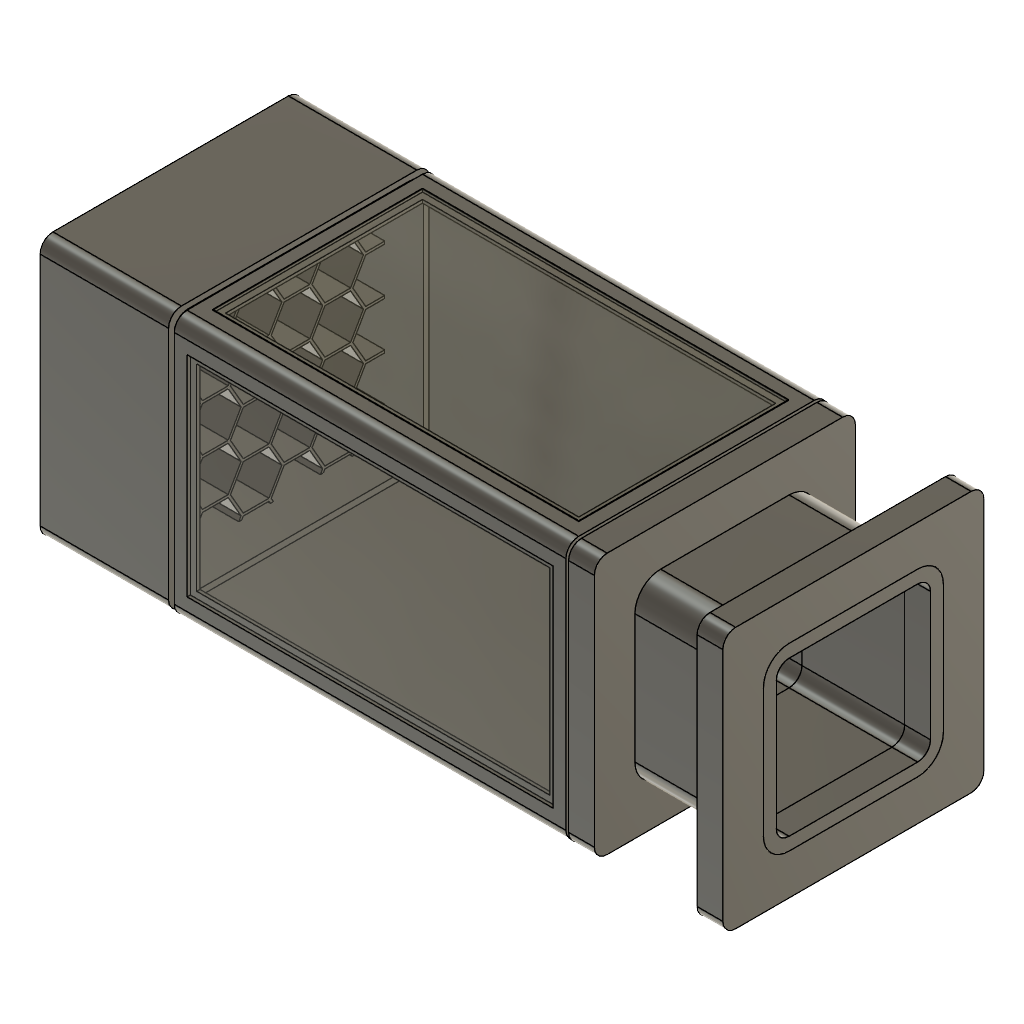
Wind Tunnel Design (Autodesk Fusion 360 design; units mm, degrees)
part number: 2026-09-10-14-34-11-708
Autodesk Fusion 360 part; units mm, degrees
sketch "Sketch6" plane through (0, 0, 0) normal (0, 1, 0) x (1, 0, 0)
  line L0 (-10, -16) -> (173.2, -16)
  line L1 (183.2, -6) -> (183.2, 177.2)
  line L2 (173.2, 187.2) -> (-10, 187.2)
  line L3 (-20, 177.2) -> (-20, -6)
  arc A0 (-20, -6) -> (-10, -16) centre (-10, -6) ccw
  arc A1 (173.2, -16) -> (183.2, -6) centre (173.2, -6) ccw
  arc A2 (183.2, 177.2) -> (173.2, 187.2) centre (173.2, 177.2) ccw
  arc A3 (-10, 187.2) -> (-20, 177.2) centre (-10, 177.2) ccw
  point P0 (-20, -16)
  point P1 (183.2, -16)
  point P2 (-20, 187.2)
  dimension "d24" = 203.2
  dimension "d25" = 203.2
  dimension "d26" = 10
  constraint horizontal L0
  constraint vertical L1
  constraint horizontal L2
  constraint vertical L3
  constraint coincident P0 L0
  constraint coincident P0 L3
  constraint tangent L0 A0
  constraint tangent L3 A0
  constraint coincident P1 L0
  constraint coincident P1 L1
  constraint tangent L0 A1
  constraint tangent L1 A1
  constraint equal A0 A1
  constraint tangent L1 A2
  constraint tangent L2 A2
  constraint equal A0 A2
  constraint coincident P2 L2
  constraint coincident P2 L3
  constraint tangent L2 A3
  constraint tangent L3 A3
  constraint equal A0 A3
  measures "d24" distance of P0 P1
  measures "d25" distance of P0 P2
  measures "d26" radius of A0
extrude "Extrude11" add sketch "Sketch6" along normal blind 100 makes body 1
move_body "Move1" bodies 1 to x (1, 0, 0) y (0, 1, 0) z (0, 0, 1) at (0, 0, 185)
move_face "MoveFace1" by (0, 0, 10) 1 faces at (47.7333, 0, 129.9333) on bodies 1
move_body "Move2" bodies 1 to x (1, 0, 0) y (0, 1, 0) z (0, 0, 1) at (0, 0, 2)
sketch "Sketch7" plane through (0, 0, 0) normal (0, -1, 0) x (1, 0, 0)
  arc A0 (-20, 9.8) -> (-10, -0.2) centre (-10, 9.8) ccw
  line L0 (-10, -0.2) -> (173.2, -0.2)
  arc A1 (173.2, -0.2) -> (183.2, 9.8) centre (173.2, 9.8) ccw
  line L1 (183.2, 9.8) -> (183.2, 193)
  arc A2 (183.2, 193) -> (173.2, 203) centre (173.2, 193) ccw
  line L2 (173.2, 203) -> (-10, 203)
  arc A3 (-10, 203) -> (-20, 193) centre (-10, 193) ccw
  line L3 (-20, 193) -> (-20, 9.8)
  line L4 (-5, 198.5) -> (168.2, 198.5)
  line L5 (178.2, 188.5) -> (178.2, 15.3)
  line L6 (168.2, 5.3) -> (-5, 5.3)
  line L7 (-15, 15.3) -> (-15, 188.5)
  arc A4 (-5, 198.5) -> (-15, 188.5) centre (-5, 188.5) ccw
  arc A5 (178.2, 188.5) -> (168.2, 198.5) centre (168.2, 188.5) ccw
  arc A6 (-15, 15.3) -> (-5, 5.3) centre (-5, 15.3) ccw
  arc A7 (168.2, 5.3) -> (178.2, 15.3) centre (168.2, 15.3) ccw
  point P0 (-15, 198.5)
  point P1 (178.2, 198.5)
  point P2 (-15, 5.3)
  dimension "d29" = 193.2
  dimension "d30" = 193.2
  dimension "d31" = 10
  dimension "d32" = 10
  constraint horizontal L4
  constraint vertical L5
  constraint horizontal L6
  constraint vertical L7
  constraint coincident P0 L4
  constraint coincident P0 L7
  constraint tangent L4 A4
  constraint tangent L7 A4
  constraint coincident P1 L4
  constraint coincident P1 L5
  constraint tangent L4 A5
  constraint tangent L5 A5
  constraint equal A4 A5
  constraint coincident P2 L6
  constraint coincident P2 L7
  constraint tangent L6 A6
  constraint tangent L7 A6
  constraint tangent L5 A7
  constraint tangent L6 A7
  constraint equal A6 A7
  measures "d29" distance of P0 P1
  measures "d30" distance of P0 P2
  measures "d31" radius of A4
  measures "d32" radius of A6
extrude "Extrude12" cut sketch "Sketch7" against normal blind 100 contours L4 L5 L6 L7 A4 A5 A6 A7 bodies 1
sketch "Sketch8" plane through (0, 0, 0) normal (0, -1, 0) x (1, 0, 0)
  line L0 (-15, 200) -> (180, 200)
  line L1 (180, 200) -> (180, 5)
  line L2 (180, 5) -> (-15, 5)
  line L3 (-15, 5) -> (-15, 200)
  line L4 (20.942, 156.3504) -> (32.4034, 176.3996)
  line L5 (32.4034, 176.3996) -> (20.771, 196.3501)
  line L6 (20.771, 196.3501) -> (-2.3228, 196.2513)
  line L7 (-2.3228, 196.2513) -> (-13.7842, 176.2022)
  line L8 (-13.7842, 176.2022) -> (-2.1518, 156.2517)
  line L9 (-2.1518, 156.2517) -> (20.942, 156.3504)
  point P0 (9.3096, 176.3009)
  dimension "d35" = 20
  constraint horizontal L0
  constraint vertical L1
  constraint horizontal L2
  constraint vertical L3
  measures "d35" distance of P0 L9
sketch "Sketch9" plane through (0, 0, 0) normal (0, -1, 0) x (1, 0, 0)
  line L0 (168.2, 5.3) -> (-5, 5.3)
  arc A0 (-15, 15.3) -> (-5, 5.3) centre (-5, 15.3) ccw
  line L1 (-15, 15.3) -> (-15, 188.5)
  arc A1 (-5, 198.5) -> (-15, 188.5) centre (-5, 188.5) ccw
  line L2 (-5, 198.5) -> (168.2, 198.5)
  arc A2 (178.2, 188.5) -> (168.2, 198.5) centre (168.2, 188.5) ccw
  line L3 (178.2, 188.5) -> (178.2, 15.3)
  arc A3 (168.2, 5.3) -> (178.2, 15.3) centre (168.2, 15.3) ccw
  arc A4 (-20, 9.8) -> (-10, -0.2) centre (-10, 9.8) ccw
  line L4 (-10, -0.2) -> (173.2, -0.2)
  arc A5 (173.2, -0.2) -> (183.2, 9.8) centre (173.2, 9.8) ccw
  line L5 (183.2, 9.8) -> (183.2, 193)
  arc A6 (183.2, 193) -> (173.2, 203) centre (173.2, 193) ccw
  line L6 (173.2, 203) -> (-10, 203)
  arc A7 (-10, 203) -> (-20, 193) centre (-10, 193) ccw
  line L7 (-20, 193) -> (-20, 9.8)
  line L8 (95.0575, 82.6796) -> (105.0575, 100.0001)
  line L9 (105.0575, 100.0001) -> (95.0575, 117.3206)
  line L10 (95.0575, 117.3206) -> (75.0575, 117.3206)
  line L11 (75.0575, 117.3206) -> (65.0575, 100.0001)
  line L12 (65.0575, 100.0001) -> (75.0575, 82.6796)
  line L13 (75.0575, 82.6796) -> (95.0575, 82.6796)
  line L14 (105.0575, 100.0001) -> (113.7178, 95.0001)
  line L15 (126.7939, 99.0019) -> (106.7939, 99.0019)
  line L16 (106.7939, 99.0019) -> (96.7939, 81.6814)
  line L17 (96.7939, 81.6814) -> (106.7939, 64.3609)
  line L18 (106.7939, 64.3609) -> (126.7939, 64.3609)
  line L19 (126.7939, 64.3609) -> (136.7939, 81.6814)
  line L20 (136.7939, 81.6814) -> (126.7939, 99.0019)
  line L21 (232.0575, -9.9499) -> (222.0575, 7.3706)
  line L22 (222.0575, 7.3706) -> (202.0575, 7.3706)
  line L23 (202.0575, 7.3706) -> (192.0575, -9.9499)
  line L24 (192.0575, -9.9499) -> (202.0575, -27.2704)
  line L25 (202.0575, -27.2704) -> (222.0575, -27.2704)
  line L26 (222.0575, -27.2704) -> (232.0575, -9.9499)
  line L27 (223.7939, -28.2686) -> (233.7939, -45.5891)
  line L28 (233.7939, -45.5891) -> (253.7939, -45.5891)
  line L29 (253.7939, -45.5891) -> (263.7939, -28.2686)
  line L30 (263.7939, -28.2686) -> (253.7939, -10.9481)
  line L31 (233.7939, -10.9481) -> (223.7939, -28.2686)
  line L32 (253.7939, -10.9481) -> (233.7939, -10.9481)
  line L33 (168.5575, -9.9499) -> (158.5575, 7.3706)
  line L34 (158.5575, 7.3706) -> (138.5575, 7.3706)
  line L35 (138.5575, 7.3706) -> (128.5575, -9.9499)
  line L36 (128.5575, -9.9499) -> (138.5575, -27.2704)
  line L37 (138.5575, -27.2704) -> (158.5575, -27.2704)
  line L38 (158.5575, -27.2704) -> (168.5575, -9.9499)
  line L39 (160.2939, -28.2686) -> (170.2939, -45.5891)
  line L40 (170.2939, -45.5891) -> (190.2939, -45.5891)
  line L41 (190.2939, -45.5891) -> (200.2939, -28.2686)
  line L42 (200.2939, -28.2686) -> (190.2939, -10.9481)
  line L43 (170.2939, -10.9481) -> (160.2939, -28.2686)
  line L44 (190.2939, -10.9481) -> (170.2939, -10.9481)
  line L45 (105.0575, -9.9499) -> (95.0575, 7.3706)
  line L46 (95.0575, 7.3706) -> (75.0575, 7.3706)
  line L47 (75.0575, 7.3706) -> (65.0575, -9.9499)
  line L48 (65.0575, -9.9499) -> (75.0575, -27.2704)
  line L49 (75.0575, -27.2704) -> (95.0575, -27.2704)
  line L50 (95.0575, -27.2704) -> (105.0575, -9.9499)
  line L51 (96.7939, -28.2686) -> (106.7939, -45.5891)
  line L52 (106.7939, -45.5891) -> (126.7939, -45.5891)
  line L53 (126.7939, -45.5891) -> (136.7939, -28.2686)
  line L54 (136.7939, -28.2686) -> (126.7939, -10.9481)
  line L55 (106.7939, -10.9481) -> (96.7939, -28.2686)
  line L56 (126.7939, -10.9481) -> (106.7939, -10.9481)
  line L57 (41.5575, -9.9499) -> (31.5575, 7.3706)
  line L58 (31.5575, 7.3706) -> (11.5575, 7.3706)
  line L59 (11.5575, 7.3706) -> (1.5575, -9.9499)
  line L60 (1.5575, -9.9499) -> (11.5575, -27.2704)
  line L61 (11.5575, -27.2704) -> (31.5575, -27.2704)
  line L62 (31.5575, -27.2704) -> (41.5575, -9.9499)
  line L63 (33.2939, -28.2686) -> (43.2939, -45.5891)
  line L64 (43.2939, -45.5891) -> (63.2939, -45.5891)
  line L65 (63.2939, -45.5891) -> (73.2939, -28.2686)
  line L66 (73.2939, -28.2686) -> (63.2939, -10.9481)
  line L67 (43.2939, -10.9481) -> (33.2939, -28.2686)
  line L68 (63.2939, -10.9481) -> (43.2939, -10.9481)
  line L69 (-21.9425, -9.9499) -> (-31.9425, 7.3706)
  line L70 (-31.9425, 7.3706) -> (-51.9425, 7.3706)
  line L71 (-51.9425, 7.3706) -> (-61.9425, -9.9499)
  line L72 (-61.9425, -9.9499) -> (-51.9425, -27.2704)
  line L73 (-51.9425, -27.2704) -> (-31.9425, -27.2704)
  line L74 (-31.9425, -27.2704) -> (-21.9425, -9.9499)
  line L75 (-30.2061, -28.2686) -> (-20.2061, -45.5891)
  line L76 (-20.2061, -45.5891) -> (-0.2061, -45.5891)
  line L77 (-0.2061, -45.5891) -> (9.7939, -28.2686)
  line L78 (9.7939, -28.2686) -> (-0.2061, -10.9481)
  line L79 (-20.2061, -10.9481) -> (-30.2061, -28.2686)
  line L80 (-0.2061, -10.9481) -> (-20.2061, -10.9481)
  line L81 (232.0575, 26.7001) -> (222.0575, 44.0206)
  line L82 (222.0575, 44.0206) -> (202.0575, 44.0206)
  line L83 (202.0575, 44.0206) -> (192.0575, 26.7001)
  line L84 (192.0575, 26.7001) -> (202.0575, 9.3796)
  line L85 (202.0575, 9.3796) -> (222.0575, 9.3796)
  line L86 (222.0575, 9.3796) -> (232.0575, 26.7001)
  line L87 (223.7939, 8.3814) -> (233.7939, -8.9391)
  line L88 (233.7939, -8.9391) -> (253.7939, -8.9391)
  line L89 (253.7939, -8.9391) -> (263.7939, 8.3814)
  line L90 (263.7939, 8.3814) -> (253.7939, 25.7019)
  line L91 (233.7939, 25.7019) -> (223.7939, 8.3814)
  line L92 (253.7939, 25.7019) -> (233.7939, 25.7019)
  line L93 (168.5575, 26.7001) -> (158.5575, 44.0206)
  line L94 (158.5575, 44.0206) -> (138.5575, 44.0206)
  line L95 (138.5575, 44.0206) -> (128.5575, 26.7001)
  line L96 (128.5575, 26.7001) -> (138.5575, 9.3796)
  line L97 (138.5575, 9.3796) -> (158.5575, 9.3796)
  line L98 (158.5575, 9.3796) -> (168.5575, 26.7001)
  line L99 (160.2939, 8.3814) -> (170.2939, -8.9391)
  line L100 (170.2939, -8.9391) -> (190.2939, -8.9391)
  line L101 (190.2939, -8.9391) -> (200.2939, 8.3814)
  line L102 (200.2939, 8.3814) -> (190.2939, 25.7019)
  line L103 (170.2939, 25.7019) -> (160.2939, 8.3814)
  line L104 (190.2939, 25.7019) -> (170.2939, 25.7019)
  line L105 (105.0575, 26.7001) -> (95.0575, 44.0206)
  line L106 (95.0575, 44.0206) -> (75.0575, 44.0206)
  line L107 (75.0575, 44.0206) -> (65.0575, 26.7001)
  line L108 (65.0575, 26.7001) -> (75.0575, 9.3796)
  line L109 (75.0575, 9.3796) -> (95.0575, 9.3796)
  line L110 (95.0575, 9.3796) -> (105.0575, 26.7001)
  line L111 (96.7939, 8.3814) -> (106.7939, -8.9391)
  line L112 (106.7939, -8.9391) -> (126.7939, -8.9391)
  line L113 (126.7939, -8.9391) -> (136.7939, 8.3814)
  line L114 (136.7939, 8.3814) -> (126.7939, 25.7019)
  line L115 (106.7939, 25.7019) -> (96.7939, 8.3814)
  line L116 (126.7939, 25.7019) -> (106.7939, 25.7019)
  line L117 (41.5575, 26.7001) -> (31.5575, 44.0206)
  line L118 (31.5575, 44.0206) -> (11.5575, 44.0206)
  line L119 (11.5575, 44.0206) -> (1.5575, 26.7001)
  line L120 (1.5575, 26.7001) -> (11.5575, 9.3796)
  line L121 (11.5575, 9.3796) -> (31.5575, 9.3796)
  line L122 (31.5575, 9.3796) -> (41.5575, 26.7001)
  line L123 (33.2939, 8.3814) -> (43.2939, -8.9391)
  line L124 (43.2939, -8.9391) -> (63.2939, -8.9391)
  line L125 (63.2939, -8.9391) -> (73.2939, 8.3814)
  line L126 (73.2939, 8.3814) -> (63.2939, 25.7019)
  line L127 (43.2939, 25.7019) -> (33.2939, 8.3814)
  line L128 (63.2939, 25.7019) -> (43.2939, 25.7019)
  line L129 (-21.9425, 26.7001) -> (-31.9425, 44.0206)
  line L130 (-31.9425, 44.0206) -> (-51.9425, 44.0206)
  line L131 (-51.9425, 44.0206) -> (-61.9425, 26.7001)
  line L132 (-61.9425, 26.7001) -> (-51.9425, 9.3796)
  line L133 (-51.9425, 9.3796) -> (-31.9425, 9.3796)
  line L134 (-31.9425, 9.3796) -> (-21.9425, 26.7001)
  line L135 (-30.2061, 8.3814) -> (-20.2061, -8.9391)
  line L136 (-20.2061, -8.9391) -> (-0.2061, -8.9391)
  line L137 (-0.2061, -8.9391) -> (9.7939, 8.3814)
  line L138 (9.7939, 8.3814) -> (-0.2061, 25.7019)
  line L139 (-20.2061, 25.7019) -> (-30.2061, 8.3814)
  line L140 (-0.2061, 25.7019) -> (-20.2061, 25.7019)
  line L141 (232.0575, 63.3501) -> (222.0575, 80.6706)
  line L142 (222.0575, 80.6706) -> (202.0575, 80.6706)
  line L143 (202.0575, 80.6706) -> (192.0575, 63.3501)
  line L144 (192.0575, 63.3501) -> (202.0575, 46.0296)
  line L145 (202.0575, 46.0296) -> (222.0575, 46.0296)
  line L146 (222.0575, 46.0296) -> (232.0575, 63.3501)
  line L147 (223.7939, 45.0314) -> (233.7939, 27.7109)
  line L148 (233.7939, 27.7109) -> (253.7939, 27.7109)
  line L149 (253.7939, 27.7109) -> (263.7939, 45.0314)
  line L150 (263.7939, 45.0314) -> (253.7939, 62.3519)
  line L151 (233.7939, 62.3519) -> (223.7939, 45.0314)
  line L152 (253.7939, 62.3519) -> (233.7939, 62.3519)
  line L153 (168.5575, 63.3501) -> (158.5575, 80.6706)
  line L154 (158.5575, 80.6706) -> (138.5575, 80.6706)
  line L155 (138.5575, 80.6706) -> (128.5575, 63.3501)
  line L156 (128.5575, 63.3501) -> (138.5575, 46.0296)
  line L157 (138.5575, 46.0296) -> (158.5575, 46.0296)
  line L158 (158.5575, 46.0296) -> (168.5575, 63.3501)
  line L159 (160.2939, 45.0314) -> (170.2939, 27.7109)
  line L160 (170.2939, 27.7109) -> (190.2939, 27.7109)
  line L161 (190.2939, 27.7109) -> (200.2939, 45.0314)
  line L162 (200.2939, 45.0314) -> (190.2939, 62.3519)
  line L163 (170.2939, 62.3519) -> (160.2939, 45.0314)
  line L164 (190.2939, 62.3519) -> (170.2939, 62.3519)
  line L165 (105.0575, 63.3501) -> (95.0575, 80.6706)
  line L166 (95.0575, 80.6706) -> (75.0575, 80.6706)
  line L167 (75.0575, 80.6706) -> (65.0575, 63.3501)
  line L168 (65.0575, 63.3501) -> (75.0575, 46.0296)
  line L169 (75.0575, 46.0296) -> (95.0575, 46.0296)
  line L170 (95.0575, 46.0296) -> (105.0575, 63.3501)
  line L171 (96.7939, 45.0314) -> (106.7939, 27.7109)
  line L172 (106.7939, 27.7109) -> (126.7939, 27.7109)
  line L173 (126.7939, 27.7109) -> (136.7939, 45.0314)
  line L174 (136.7939, 45.0314) -> (126.7939, 62.3519)
  line L175 (106.7939, 62.3519) -> (96.7939, 45.0314)
  line L176 (126.7939, 62.3519) -> (106.7939, 62.3519)
  line L177 (41.5575, 63.3501) -> (31.5575, 80.6706)
  line L178 (31.5575, 80.6706) -> (11.5575, 80.6706)
  line L179 (11.5575, 80.6706) -> (1.5575, 63.3501)
  line L180 (1.5575, 63.3501) -> (11.5575, 46.0296)
  line L181 (11.5575, 46.0296) -> (31.5575, 46.0296)
  line L182 (31.5575, 46.0296) -> (41.5575, 63.3501)
  line L183 (33.2939, 45.0314) -> (43.2939, 27.7109)
  line L184 (43.2939, 27.7109) -> (63.2939, 27.7109)
  line L185 (63.2939, 27.7109) -> (73.2939, 45.0314)
  line L186 (73.2939, 45.0314) -> (63.2939, 62.3519)
  line L187 (43.2939, 62.3519) -> (33.2939, 45.0314)
  line L188 (63.2939, 62.3519) -> (43.2939, 62.3519)
  line L189 (-21.9425, 63.3501) -> (-31.9425, 80.6706)
  line L190 (-31.9425, 80.6706) -> (-51.9425, 80.6706)
  line L191 (-51.9425, 80.6706) -> (-61.9425, 63.3501)
  line L192 (-61.9425, 63.3501) -> (-51.9425, 46.0296)
  line L193 (-51.9425, 46.0296) -> (-31.9425, 46.0296)
  line L194 (-31.9425, 46.0296) -> (-21.9425, 63.3501)
  line L195 (-30.2061, 45.0314) -> (-20.2061, 27.7109)
  line L196 (-20.2061, 27.7109) -> (-0.2061, 27.7109)
  line L197 (-0.2061, 27.7109) -> (9.7939, 45.0314)
  line L198 (9.7939, 45.0314) -> (-0.2061, 62.3519)
  line L199 (-20.2061, 62.3519) -> (-30.2061, 45.0314)
  line L200 (-0.2061, 62.3519) -> (-20.2061, 62.3519)
  line L201 (232.0575, 100.0001) -> (222.0575, 117.3206)
  line L202 (222.0575, 117.3206) -> (202.0575, 117.3206)
  line L203 (202.0575, 117.3206) -> (192.0575, 100.0001)
  line L204 (192.0575, 100.0001) -> (202.0575, 82.6796)
  line L205 (202.0575, 82.6796) -> (222.0575, 82.6796)
  line L206 (222.0575, 82.6796) -> (232.0575, 100.0001)
  line L207 (223.7939, 81.6814) -> (233.7939, 64.3609)
  line L208 (233.7939, 64.3609) -> (253.7939, 64.3609)
  line L209 (253.7939, 64.3609) -> (263.7939, 81.6814)
  line L210 (263.7939, 81.6814) -> (253.7939, 99.0019)
  line L211 (233.7939, 99.0019) -> (223.7939, 81.6814)
  line L212 (253.7939, 99.0019) -> (233.7939, 99.0019)
  line L213 (168.5575, 100.0001) -> (158.5575, 117.3206)
  line L214 (158.5575, 117.3206) -> (138.5575, 117.3206)
  line L215 (138.5575, 117.3206) -> (128.5575, 100.0001)
  line L216 (128.5575, 100.0001) -> (138.5575, 82.6796)
  line L217 (138.5575, 82.6796) -> (158.5575, 82.6796)
  line L218 (158.5575, 82.6796) -> (168.5575, 100.0001)
  line L219 (160.2939, 81.6814) -> (170.2939, 64.3609)
  line L220 (170.2939, 64.3609) -> (190.2939, 64.3609)
  line L221 (190.2939, 64.3609) -> (200.2939, 81.6814)
  line L222 (200.2939, 81.6814) -> (190.2939, 99.0019)
  line L223 (170.2939, 99.0019) -> (160.2939, 81.6814)
  line L224 (190.2939, 99.0019) -> (170.2939, 99.0019)
  line L225 (41.5575, 100.0001) -> (31.5575, 117.3206)
  line L226 (31.5575, 117.3206) -> (11.5575, 117.3206)
  line L227 (11.5575, 117.3206) -> (1.5575, 100.0001)
  line L228 (1.5575, 100.0001) -> (11.5575, 82.6796)
  line L229 (11.5575, 82.6796) -> (31.5575, 82.6796)
  line L230 (31.5575, 82.6796) -> (41.5575, 100.0001)
  line L231 (33.2939, 81.6814) -> (43.2939, 64.3609)
  line L232 (43.2939, 64.3609) -> (63.2939, 64.3609)
  line L233 (63.2939, 64.3609) -> (73.2939, 81.6814)
  line L234 (73.2939, 81.6814) -> (63.2939, 99.0019)
  line L235 (43.2939, 99.0019) -> (33.2939, 81.6814)
  line L236 (63.2939, 99.0019) -> (43.2939, 99.0019)
  line L237 (-21.9425, 100.0001) -> (-31.9425, 117.3206)
  line L238 (-31.9425, 117.3206) -> (-51.9425, 117.3206)
  line L239 (-51.9425, 117.3206) -> (-61.9425, 100.0001)
  line L240 (-61.9425, 100.0001) -> (-51.9425, 82.6796)
  line L241 (-51.9425, 82.6796) -> (-31.9425, 82.6796)
  line L242 (-31.9425, 82.6796) -> (-21.9425, 100.0001)
  line L243 (-30.2061, 81.6814) -> (-20.2061, 64.3609)
  line L244 (-20.2061, 64.3609) -> (-0.2061, 64.3609)
  line L245 (-0.2061, 64.3609) -> (9.7939, 81.6814)
  line L246 (9.7939, 81.6814) -> (-0.2061, 99.0019)
  line L247 (-20.2061, 99.0019) -> (-30.2061, 81.6814)
  line L248 (-0.2061, 99.0019) -> (-20.2061, 99.0019)
  line L249 (232.0575, 136.6501) -> (222.0575, 153.9706)
  line L250 (222.0575, 153.9706) -> (202.0575, 153.9706)
  line L251 (202.0575, 153.9706) -> (192.0575, 136.6501)
  line L252 (192.0575, 136.6501) -> (202.0575, 119.3296)
  line L253 (202.0575, 119.3296) -> (222.0575, 119.3296)
  line L254 (222.0575, 119.3296) -> (232.0575, 136.6501)
  line L255 (223.7939, 118.3314) -> (233.7939, 101.0109)
  line L256 (233.7939, 101.0109) -> (253.7939, 101.0109)
  line L257 (253.7939, 101.0109) -> (263.7939, 118.3314)
  line L258 (263.7939, 118.3314) -> (253.7939, 135.6519)
  line L259 (233.7939, 135.6519) -> (223.7939, 118.3314)
  line L260 (253.7939, 135.6519) -> (233.7939, 135.6519)
  line L261 (168.5575, 136.6501) -> (158.5575, 153.9706)
  line L262 (158.5575, 153.9706) -> (138.5575, 153.9706)
  line L263 (138.5575, 153.9706) -> (128.5575, 136.6501)
  line L264 (128.5575, 136.6501) -> (138.5575, 119.3296)
  line L265 (138.5575, 119.3296) -> (158.5575, 119.3296)
  line L266 (158.5575, 119.3296) -> (168.5575, 136.6501)
  line L267 (160.2939, 118.3314) -> (170.2939, 101.0109)
  line L268 (170.2939, 101.0109) -> (190.2939, 101.0109)
  line L269 (190.2939, 101.0109) -> (200.2939, 118.3314)
  line L270 (200.2939, 118.3314) -> (190.2939, 135.6519)
  line L271 (170.2939, 135.6519) -> (160.2939, 118.3314)
  line L272 (190.2939, 135.6519) -> (170.2939, 135.6519)
  line L273 (105.0575, 136.6501) -> (95.0575, 153.9706)
  line L274 (95.0575, 153.9706) -> (75.0575, 153.9706)
  line L275 (75.0575, 153.9706) -> (65.0575, 136.6501)
  line L276 (65.0575, 136.6501) -> (75.0575, 119.3296)
  line L277 (75.0575, 119.3296) -> (95.0575, 119.3296)
  line L278 (95.0575, 119.3296) -> (105.0575, 136.6501)
  line L279 (96.7939, 118.3314) -> (106.7939, 101.0109)
  line L280 (106.7939, 101.0109) -> (126.7939, 101.0109)
  line L281 (126.7939, 101.0109) -> (136.7939, 118.3314)
  line L282 (136.7939, 118.3314) -> (126.7939, 135.6519)
  line L283 (106.7939, 135.6519) -> (96.7939, 118.3314)
  line L284 (126.7939, 135.6519) -> (106.7939, 135.6519)
  line L285 (41.5575, 136.6501) -> (31.5575, 153.9706)
  line L286 (31.5575, 153.9706) -> (11.5575, 153.9706)
  line L287 (11.5575, 153.9706) -> (1.5575, 136.6501)
  line L288 (1.5575, 136.6501) -> (11.5575, 119.3296)
  line L289 (11.5575, 119.3296) -> (31.5575, 119.3296)
  line L290 (31.5575, 119.3296) -> (41.5575, 136.6501)
  line L291 (33.2939, 118.3314) -> (43.2939, 101.0109)
  line L292 (43.2939, 101.0109) -> (63.2939, 101.0109)
  line L293 (63.2939, 101.0109) -> (73.2939, 118.3314)
  line L294 (73.2939, 118.3314) -> (63.2939, 135.6519)
  line L295 (43.2939, 135.6519) -> (33.2939, 118.3314)
  line L296 (63.2939, 135.6519) -> (43.2939, 135.6519)
  line L297 (-21.9425, 136.6501) -> (-31.9425, 153.9706)
  line L298 (-31.9425, 153.9706) -> (-51.9425, 153.9706)
  line L299 (-51.9425, 153.9706) -> (-61.9425, 136.6501)
  line L300 (-61.9425, 136.6501) -> (-51.9425, 119.3296)
  line L301 (-51.9425, 119.3296) -> (-31.9425, 119.3296)
  line L302 (-31.9425, 119.3296) -> (-21.9425, 136.6501)
  line L303 (-30.2061, 118.3314) -> (-20.2061, 101.0109)
  line L304 (-20.2061, 101.0109) -> (-0.2061, 101.0109)
  line L305 (-0.2061, 101.0109) -> (9.7939, 118.3314)
  line L306 (9.7939, 118.3314) -> (-0.2061, 135.6519)
  line L307 (-20.2061, 135.6519) -> (-30.2061, 118.3314)
  line L308 (-0.2061, 135.6519) -> (-20.2061, 135.6519)
  line L309 (232.0575, 173.3001) -> (222.0575, 190.6206)
  line L310 (222.0575, 190.6206) -> (202.0575, 190.6206)
  line L311 (202.0575, 190.6206) -> (192.0575, 173.3001)
  line L312 (192.0575, 173.3001) -> (202.0575, 155.9796)
  line L313 (202.0575, 155.9796) -> (222.0575, 155.9796)
  line L314 (222.0575, 155.9796) -> (232.0575, 173.3001)
  line L315 (223.7939, 154.9814) -> (233.7939, 137.6609)
  line L316 (233.7939, 137.6609) -> (253.7939, 137.6609)
  line L317 (253.7939, 137.6609) -> (263.7939, 154.9814)
  line L318 (263.7939, 154.9814) -> (253.7939, 172.3019)
  line L319 (233.7939, 172.3019) -> (223.7939, 154.9814)
  line L320 (253.7939, 172.3019) -> (233.7939, 172.3019)
  line L321 (168.5575, 173.3001) -> (158.5575, 190.6206)
  line L322 (158.5575, 190.6206) -> (138.5575, 190.6206)
  line L323 (138.5575, 190.6206) -> (128.5575, 173.3001)
  line L324 (128.5575, 173.3001) -> (138.5575, 155.9796)
  line L325 (138.5575, 155.9796) -> (158.5575, 155.9796)
  line L326 (158.5575, 155.9796) -> (168.5575, 173.3001)
  line L327 (160.2939, 154.9814) -> (170.2939, 137.6609)
  line L328 (170.2939, 137.6609) -> (190.2939, 137.6609)
  line L329 (190.2939, 137.6609) -> (200.2939, 154.9814)
  line L330 (200.2939, 154.9814) -> (190.2939, 172.3019)
  line L331 (170.2939, 172.3019) -> (160.2939, 154.9814)
  line L332 (190.2939, 172.3019) -> (170.2939, 172.3019)
  line L333 (105.0575, 173.3001) -> (95.0575, 190.6206)
  line L334 (95.0575, 190.6206) -> (75.0575, 190.6206)
  line L335 (75.0575, 190.6206) -> (65.0575, 173.3001)
  line L336 (65.0575, 173.3001) -> (75.0575, 155.9796)
  line L337 (75.0575, 155.9796) -> (95.0575, 155.9796)
  line L338 (95.0575, 155.9796) -> (105.0575, 173.3001)
  line L339 (96.7939, 154.9814) -> (106.7939, 137.6609)
  line L340 (106.7939, 137.6609) -> (126.7939, 137.6609)
  line L341 (126.7939, 137.6609) -> (136.7939, 154.9814)
  line L342 (136.7939, 154.9814) -> (126.7939, 172.3019)
  line L343 (106.7939, 172.3019) -> (96.7939, 154.9814)
  line L344 (126.7939, 172.3019) -> (106.7939, 172.3019)
  line L345 (41.5575, 173.3001) -> (31.5575, 190.6206)
  line L346 (31.5575, 190.6206) -> (11.5575, 190.6206)
  line L347 (11.5575, 190.6206) -> (1.5575, 173.3001)
  line L348 (1.5575, 173.3001) -> (11.5575, 155.9796)
  line L349 (11.5575, 155.9796) -> (31.5575, 155.9796)
  line L350 (31.5575, 155.9796) -> (41.5575, 173.3001)
  line L351 (33.2939, 154.9814) -> (43.2939, 137.6609)
  line L352 (43.2939, 137.6609) -> (63.2939, 137.6609)
  line L353 (63.2939, 137.6609) -> (73.2939, 154.9814)
  line L354 (73.2939, 154.9814) -> (63.2939, 172.3019)
  line L355 (43.2939, 172.3019) -> (33.2939, 154.9814)
  line L356 (63.2939, 172.3019) -> (43.2939, 172.3019)
  line L357 (-21.9425, 173.3001) -> (-31.9425, 190.6206)
  line L358 (-31.9425, 190.6206) -> (-51.9425, 190.6206)
  line L359 (-51.9425, 190.6206) -> (-61.9425, 173.3001)
  line L360 (-61.9425, 173.3001) -> (-51.9425, 155.9796)
  line L361 (-51.9425, 155.9796) -> (-31.9425, 155.9796)
  line L362 (-31.9425, 155.9796) -> (-21.9425, 173.3001)
  line L363 (-30.2061, 154.9814) -> (-20.2061, 137.6609)
  line L364 (-20.2061, 137.6609) -> (-0.2061, 137.6609)
  line L365 (-0.2061, 137.6609) -> (9.7939, 154.9814)
  line L366 (9.7939, 154.9814) -> (-0.2061, 172.3019)
  line L367 (-20.2061, 172.3019) -> (-30.2061, 154.9814)
  line L368 (-0.2061, 172.3019) -> (-20.2061, 172.3019)
  line L369 (232.0575, 209.9501) -> (222.0575, 227.2706)
  line L370 (222.0575, 227.2706) -> (202.0575, 227.2706)
  line L371 (202.0575, 227.2706) -> (192.0575, 209.9501)
  line L372 (192.0575, 209.9501) -> (202.0575, 192.6296)
  line L373 (202.0575, 192.6296) -> (222.0575, 192.6296)
  line L374 (222.0575, 192.6296) -> (232.0575, 209.9501)
  line L375 (223.7939, 191.6314) -> (233.7939, 174.3109)
  line L376 (233.7939, 174.3109) -> (253.7939, 174.3109)
  line L377 (253.7939, 174.3109) -> (263.7939, 191.6314)
  line L378 (263.7939, 191.6314) -> (253.7939, 208.9519)
  line L379 (233.7939, 208.9519) -> (223.7939, 191.6314)
  line L380 (253.7939, 208.9519) -> (233.7939, 208.9519)
  line L381 (168.5575, 209.9501) -> (158.5575, 227.2706)
  line L382 (158.5575, 227.2706) -> (138.5575, 227.2706)
  line L383 (138.5575, 227.2706) -> (128.5575, 209.9501)
  line L384 (128.5575, 209.9501) -> (138.5575, 192.6296)
  line L385 (138.5575, 192.6296) -> (158.5575, 192.6296)
  line L386 (158.5575, 192.6296) -> (168.5575, 209.9501)
  line L387 (160.2939, 191.6314) -> (170.2939, 174.3109)
  line L388 (170.2939, 174.3109) -> (190.2939, 174.3109)
  line L389 (190.2939, 174.3109) -> (200.2939, 191.6314)
  line L390 (200.2939, 191.6314) -> (190.2939, 208.9519)
  line L391 (170.2939, 208.9519) -> (160.2939, 191.6314)
  line L392 (190.2939, 208.9519) -> (170.2939, 208.9519)
  line L393 (105.0575, 209.9501) -> (95.0575, 227.2706)
  line L394 (95.0575, 227.2706) -> (75.0575, 227.2706)
  line L395 (75.0575, 227.2706) -> (65.0575, 209.9501)
  line L396 (65.0575, 209.9501) -> (75.0575, 192.6296)
  line L397 (75.0575, 192.6296) -> (95.0575, 192.6296)
  line L398 (95.0575, 192.6296) -> (105.0575, 209.9501)
  line L399 (96.7939, 191.6314) -> (106.7939, 174.3109)
  line L400 (106.7939, 174.3109) -> (126.7939, 174.3109)
  line L401 (126.7939, 174.3109) -> (136.7939, 191.6314)
  line L402 (136.7939, 191.6314) -> (126.7939, 208.9519)
  line L403 (106.7939, 208.9519) -> (96.7939, 191.6314)
  line L404 (126.7939, 208.9519) -> (106.7939, 208.9519)
  line L405 (41.5575, 209.9501) -> (31.5575, 227.2706)
  line L406 (31.5575, 227.2706) -> (11.5575, 227.2706)
  line L407 (11.5575, 227.2706) -> (1.5575, 209.9501)
  line L408 (1.5575, 209.9501) -> (11.5575, 192.6296)
  line L409 (11.5575, 192.6296) -> (31.5575, 192.6296)
  line L410 (31.5575, 192.6296) -> (41.5575, 209.9501)
  line L411 (33.2939, 191.6314) -> (43.2939, 174.3109)
  line L412 (43.2939, 174.3109) -> (63.2939, 174.3109)
  line L413 (63.2939, 174.3109) -> (73.2939, 191.6314)
  line L414 (73.2939, 191.6314) -> (63.2939, 208.9519)
  line L415 (43.2939, 208.9519) -> (33.2939, 191.6314)
  line L416 (63.2939, 208.9519) -> (43.2939, 208.9519)
  line L417 (-21.9425, 209.9501) -> (-31.9425, 227.2706)
  line L418 (-31.9425, 227.2706) -> (-51.9425, 227.2706)
  line L419 (-51.9425, 227.2706) -> (-61.9425, 209.9501)
  line L420 (-61.9425, 209.9501) -> (-51.9425, 192.6296)
  line L421 (-51.9425, 192.6296) -> (-31.9425, 192.6296)
  line L422 (-31.9425, 192.6296) -> (-21.9425, 209.9501)
  line L423 (-30.2061, 191.6314) -> (-20.2061, 174.3109)
  line L424 (-20.2061, 174.3109) -> (-0.2061, 174.3109)
  line L425 (-0.2061, 174.3109) -> (9.7939, 191.6314)
  line L426 (9.7939, 191.6314) -> (-0.2061, 208.9519)
  line L427 (-20.2061, 208.9519) -> (-30.2061, 191.6314)
  line L428 (-0.2061, 208.9519) -> (-20.2061, 208.9519)
  point P0 (85.0575, 100.0001)
  dimension "d38" = 20
  dimension "d40" = 10
  dimension "d43" = -63.5
  dimension "d44" = 36.65
  constraint horizontal L13
  constraint horizontal L18
  measures "d38" distance of L8.start P0
  measures "d40" distance of L8.end L14.end
extrude "Extrude14" add sketch "Sketch9" against normal blind 70 contours L0 L1 L2 L3 L33 L34 L35 L45 L46 L47 L57 L58 L59 L99 L103 L104 L111 L113 L114 L115 L116 L123 L125 L126 L127 L128 L137 L138 L140 L159 L160 L163 L164 L196 L197 L198 L200 L219 L220 L223 L224 L244 L245 L246 L248 L267 L268 L271 L272 L304 L305 L306 L308 L327 L328 L331 L332 L364 L365 L366 L368 L384 L385 L386 L387 L388 L391 L396 L397 L398 L399 L400 L401 L402 L403 L408 L409 L410 L411 L412 L413 L414 L415 L424 L425 L426 bodies 1
move_body "Move3" bodies 1 to x (0, -1, 0) y (1, 0, 0) z (0, 0, 1) at (-213.8781, 228.2, 151.0139)
sketch "Sketch12" plane through (-113.8781, 0, 0) normal (1, 0, 0) x (0, 1, 0)
  line L0 (233.2, 156.3139) -> (60, 156.3139)
  arc A0 (50, 166.3139) -> (60, 156.3139) centre (60, 166.3139) ccw
  line L1 (50, 166.3139) -> (50, 339.5139)
  arc A1 (60, 349.5139) -> (50, 339.5139) centre (60, 339.5139) ccw
  line L2 (60, 349.5139) -> (233.2, 349.5139)
  arc A2 (243.2, 339.5139) -> (233.2, 349.5139) centre (233.2, 339.5139) ccw
  line L3 (243.2, 339.5139) -> (243.2, 166.3139)
  arc A3 (233.2, 156.3139) -> (243.2, 166.3139) centre (233.2, 166.3139) ccw
  arc A4 (238.2, 150.8139) -> (248.2, 160.8139) centre (238.2, 160.8139) ccw
  line L4 (248.2, 160.8139) -> (248.2, 344.0139)
  arc A5 (248.2, 344.0139) -> (238.2, 354.0139) centre (238.2, 344.0139) ccw
  line L5 (238.2, 354.0139) -> (55, 354.0139)
  arc A6 (55, 354.0139) -> (45, 344.0139) centre (55, 344.0139) ccw
  line L6 (45, 344.0139) -> (45, 160.8139)
  arc A7 (45, 160.8139) -> (55, 150.8139) centre (55, 160.8139) ccw
  line L7 (55, 150.8139) -> (238.2, 150.8139)
  line L8 (55, 354.0139) -> (238.2, 354.0139)
  line L9 (248.2, 344.0139) -> (248.2, 160.8139)
  line L10 (238.2, 150.8139) -> (55, 150.8139)
  line L11 (45, 160.8139) -> (45, 344.0139)
  arc A8 (55, 354.0139) -> (45, 344.0139) centre (55, 344.0139) ccw
  arc A9 (248.2, 344.0139) -> (238.2, 354.0139) centre (238.2, 344.0139) ccw
  arc A10 (238.2, 150.8139) -> (248.2, 160.8139) centre (238.2, 160.8139) ccw
  arc A11 (45, 160.8139) -> (55, 150.8139) centre (55, 160.8139) ccw
  point P0 (45, 354.0139)
  point P1 (248.2, 354.0139)
  point P2 (45, 150.8139)
  dimension "d54" = 203.2
  dimension "d55" = 203.2
  dimension "d56" = 10
  constraint horizontal L8
  constraint vertical L9
  constraint horizontal L10
  constraint vertical L11
  constraint coincident P0 L8
  constraint coincident P0 L11
  constraint tangent L8 A8
  constraint tangent L11 A8
  constraint coincident P1 L8
  constraint coincident P1 L9
  constraint tangent L8 A9
  constraint tangent L9 A9
  constraint equal A8 A9
  constraint tangent L9 A10
  constraint tangent L10 A10
  constraint equal A8 A10
  constraint coincident P2 L10
  constraint coincident P2 L11
  constraint tangent L10 A11
  constraint tangent L11 A11
  constraint equal A8 A11
  measures "d54" distance of P0 P1
  measures "d55" distance of P0 P2
  measures "d56" radius of A8
extrude "Extrude15" add sketch "Sketch12" along normal blind 305.8 bodies 1
extrude "Extrude16" cut sketch "Sketch12" along normal blind 1 contours L0 A0 L1 A1 L2 A2 L3 A3 | A4 L4 A5 L5 A6 L6 A7 L7 L8 L9 L10 L11 A8 A9 A10 A11 bodies 1 makes body 2 at (-147.2114, 45, 282.9473)
move_body "Move4" bodies 1 to x (1, 0, 0) y (0, 1, 0) z (0, 0, 1) at (-1, 0, 0)
move_body "Move5" bodies 1 2 to x (1, 0, 0) y (0, 1, 0) z (0, 0, 1) at (0, -87.5, -151.5544)
move_body "Move6" bodies 1 to x (1, 0, 0) y (0, 1, 0) z (0, 0, 1) at (150, 0, 0)
move_body "Move7" bodies 2 1 to x (1, 0, 0) y (0, 1, 0) z (0, 0, 1) at (0, 100, 0)
move_body "Move8" bodies 1 to x (1, 0, 0) y (0, 1, 0) z (0, 0, 1) at (0, -310, 0)
move_body "Move9" bodies 1 to x (1, 0, 0) y (0, 1, 0) z (0, 0, 1) at (0, 300, 0)
move_body "Move10" bodies 2 to x (1, 0, 0) y (0, 1, 0) z (0, 0, 1) at (0, -10, 0)
move_face "MoveFace2" by (125, 0, 0) 1 faces at (-147.2114, 118.5667, 202.4595) on bodies 2
move_body "Move11" bodies 2 to x (1, 0, 0) y (0, 1, 0) z (0, 0, 1) at (150, 0, 0)
move_body "Move12" bodies 1 2 to x (1, 0, 0) y (0, 1, 0) z (0, 0, 1) at (-134.2906, -138.36, 138.36)
move_body "Move13" bodies 1 2 to x (1, 0, 0) y (0, 1, 0) z (0, 0, 1) at (0, 75, -129.9038)
move_body "Move14" bodies 2 1 to x (1, 0, 0) y (0, 1, 0) z (0, 0, 1) at (0, -75, 0)
move_body "Move15" bodies 2 1 to x (1, 0, 0) y (0, 1, 0) z (0, 0, 1) at (0, 0, -7.7)
sketch "Sketch14" plane through (206.6314, 0, 0) normal (1, 0, 0) x (0, 1, 0)
  arc A0 (-85.86, 15.5157) -> (-75.86, 5.5157) centre (-75.86, 15.5157) ccw
  line L0 (-85.86, 15.5157) -> (-85.86, 188.7157)
  arc A1 (-75.86, 198.7157) -> (-85.86, 188.7157) centre (-75.86, 188.7157) ccw
  line L1 (-75.86, 198.7157) -> (97.34, 198.7157)
  arc A2 (107.34, 188.7157) -> (97.34, 198.7157) centre (97.34, 188.7157) ccw
  line L2 (107.34, 188.7157) -> (107.34, 15.5157)
  arc A3 (97.34, 5.5157) -> (107.34, 15.5157) centre (97.34, 15.5157) ccw
  line L3 (97.34, 5.5157) -> (-75.86, 5.5157)
  arc A4 (-80.86, 203.2157) -> (-90.86, 193.2157) centre (-80.86, 193.2157) ccw
  line L4 (-90.86, 193.2157) -> (-90.86, 10.0157)
  arc A5 (-90.86, 10.0157) -> (-80.86, 0.0157) centre (-80.86, 10.0157) ccw
  line L5 (-80.86, 0.0157) -> (102.34, 0.0157)
  arc A6 (102.34, 0.0157) -> (112.34, 10.0157) centre (102.34, 10.0157) ccw
  line L6 (112.34, 10.0157) -> (112.34, 193.2157)
  arc A7 (112.34, 193.2157) -> (102.34, 203.2157) centre (102.34, 193.2157) ccw
  line L7 (102.34, 203.2157) -> (-80.86, 203.2157)
sketch "Sketch16" plane through (0, 0, 5) normal (0, 0, 1) x (-1, 0, 0)
sketch "Sketch17" plane through (0, 0, 0) normal (0, 0, 1) x (1, 0, 0)
  line L0 (-495, 125) -> (-405, 125)
  line L1 (-400, 120) -> (-400, 30)
  line L2 (-405, 25) -> (-495, 25)
  line L3 (-500, 30) -> (-500, 120)
  arc A0 (-495, 125) -> (-500, 120) centre (-495, 120) ccw
  arc A1 (-400, 120) -> (-405, 125) centre (-405, 120) ccw
  arc A2 (-405, 25) -> (-400, 30) centre (-405, 30) ccw
  arc A3 (-500, 30) -> (-495, 25) centre (-495, 30) ccw
  point P0 (-500, 125)
  point P1 (-400, 125)
  point P2 (-500, 25)
  dimension "d79" = 100
  dimension "d80" = 100
  dimension "d81" = 5
  constraint horizontal L0
  constraint vertical L1
  constraint horizontal L2
  constraint vertical L3
  constraint coincident P0 L0
  constraint coincident P0 L3
  constraint tangent L0 A0
  constraint tangent L3 A0
  constraint coincident P1 L0
  constraint coincident P1 L1
  constraint tangent L0 A1
  constraint tangent L1 A1
  constraint equal A0 A1
  constraint tangent L1 A2
  constraint tangent L2 A2
  constraint equal A0 A2
  constraint coincident P2 L2
  constraint coincident P2 L3
  constraint tangent L2 A3
  constraint tangent L3 A3
  constraint equal A0 A3
  measures "d79" distance of P0 P1
  measures "d80" distance of P0 P2
  measures "d81" radius of A0
sketch "Sketch18" plane through (0, 0, 5) normal (0, 0, 1) x (-1, 0, 0)
  arc A0 (495, -125) -> (500, -120) centre (495, -120) ccw
  line L0 (500, -120) -> (500, -30)
  arc A1 (500, -30) -> (495, -25) centre (495, -30) ccw
  line L1 (495, -25) -> (405, -25)
  arc A2 (405, -25) -> (400, -30) centre (405, -30) ccw
  line L2 (400, -30) -> (400, -120)
  arc A3 (400, -120) -> (405, -125) centre (405, -120) ccw
  line L3 (405, -125) -> (495, -125)
  line L4 (490, -30) -> (410, -30)
  line L5 (405, -35) -> (405, -115)
  line L6 (410, -120) -> (490, -120)
  line L7 (495, -115) -> (495, -35)
  arc A4 (490, -120) -> (495, -115) centre (490, -115) ccw
  arc A5 (405, -115) -> (410, -120) centre (410, -115) ccw
  arc A6 (410, -30) -> (405, -35) centre (410, -35) ccw
  arc A7 (495, -35) -> (490, -30) centre (490, -35) ccw
  dimension "d85" = 5
  dimension "d86" = 5
  dimension "d87" = 5
  dimension "d88" = 5
  dimension "d89" = 5
  constraint tangent L6 A4
  constraint tangent L7 A4
  constraint tangent L5 A5
  constraint tangent L6 A5
  constraint equal A4 A5
  constraint tangent L4 A6
  constraint tangent L5 A6
  constraint equal A4 A6
  constraint tangent L4 A7
  constraint tangent L7 A7
  constraint equal A4 A7
  measures "d85" distance of L1 L4
  measures "d86" distance of L2 L5
  measures "d87" distance of L3 L6
  measures "d88" distance of L0 L7
  measures "d89" radius of A4
sketch "Sketch19" plane through (-400, 0, 0) normal (1, 0, 0) x (0, 1, 0)
  line L0 (120, 5) -> (120, 155)
  line L1 (120, 155) -> (30, 155)
  line L2 (30, 155) -> (30, 5)
  line L3 (30, 5) -> (120, 5)
sketch "Sketch20" plane through (-400, 0, 0) normal (1, 0, 0) x (0, 1, 0)
  line L0 (270, 5) -> (270, 155)
  line L1 (270, 155) -> (180, 155)
  line L2 (180, 155) -> (180, 5)
  circle A0 centre (225, 30) radius 10
  circle A1 centre (225, 30) radius 12
  line L3 (180, 5) -> (270, 5)
  dimension "d92" = 20
  dimension "d93" = 2
  measures "d92" diameter of A0
sketch "Sketch21" plane through (0, 0, 155) normal (0, 0, 1) x (-1, 0, 0)
  arc A0 (495, -185) -> (490, -180) centre (490, -185) ccw
  line L0 (495, -185) -> (495, -265)
  arc A1 (490, -270) -> (495, -265) centre (490, -265) ccw
  line L1 (490, -270) -> (410, -270)
  arc A2 (405, -265) -> (410, -270) centre (410, -265) ccw
  line L2 (405, -265) -> (405, -185)
  arc A3 (410, -180) -> (405, -185) centre (410, -185) ccw
  line L3 (410, -180) -> (490, -180)
  line L4 (405, -275) -> (495, -275)
  arc A4 (495, -275) -> (500, -270) centre (495, -270) ccw
  line L5 (500, -270) -> (500, -180)
  arc A5 (500, -180) -> (495, -175) centre (495, -180) ccw
  line L6 (495, -175) -> (405, -175)
  arc A6 (405, -175) -> (400, -180) centre (405, -180) ccw
  line L7 (400, -180) -> (400, -270)
  arc A7 (400, -270) -> (405, -275) centre (405, -270) ccw
sketch "Sketch22" plane through (-500, 0, 0) normal (-1, 0, 0) x (0, -1, 0)
  line L0 (-180, 5) -> (-180, 155)
  line L1 (-180, 155) -> (-270, 155)
  line L2 (-270, 155) -> (-270, 5)
  line L3 (-230, 155) -> (-220, 155)
  line L4 (-220, 155) -> (-220, 145)
  line L5 (-220, 145) -> (-230, 145)
  line L6 (-230, 145) -> (-230, 155)
  line L7 (-270, 5) -> (-180, 5)
  constraint horizontal L3
  constraint vertical L4
  constraint horizontal L5
  constraint vertical L6
  constraint coincident L1 L3.start
sketch "Sketch23" plane through (0, 0, 155) normal (0, 0, 1) x (-1, 0, 0)
  circle A0 centre (450, -225) radius 70.7107
move_body "Move17" bodies 1 to x (1, 0, 0) y (0, 1, 0) z (0, 0, 1) at (200, 0, 0)
sketch "Sketch25" plane through (406.6314, 0, 0) normal (1, 0, 0) x (0, 1, 0)
  arc A0 (-85.86, 15.5157) -> (-75.86, 5.5157) centre (-75.86, 15.5157) ccw
  line L0 (-85.86, 15.5157) -> (-85.86, 188.7157)
  arc A1 (-75.86, 198.7157) -> (-85.86, 188.7157) centre (-75.86, 188.7157) ccw
  line L1 (-75.86, 198.7157) -> (97.34, 198.7157)
  arc A2 (107.34, 188.7157) -> (97.34, 198.7157) centre (97.34, 188.7157) ccw
  line L2 (107.34, 188.7157) -> (107.34, 15.5157)
  arc A3 (97.34, 5.5157) -> (107.34, 15.5157) centre (97.34, 15.5157) ccw
  line L3 (97.34, 5.5157) -> (-75.86, 5.5157)
  arc A4 (-80.86, 203.2157) -> (-90.86, 193.2157) centre (-80.86, 193.2157) ccw
  line L4 (-90.86, 193.2157) -> (-90.86, 10.0157)
  arc A5 (-90.86, 10.0157) -> (-80.86, 0.0157) centre (-80.86, 10.0157) ccw
  line L5 (-80.86, 0.0157) -> (102.34, 0.0157)
  arc A6 (102.34, 0.0157) -> (112.34, 10.0157) centre (102.34, 10.0157) ccw
  line L6 (112.34, 10.0157) -> (112.34, 193.2157)
  arc A7 (112.34, 193.2157) -> (102.34, 203.2157) centre (102.34, 193.2157) ccw
  line L7 (102.34, 203.2157) -> (-80.86, 203.2157)
  line L8 (250, 200) -> (370, 200)
  line L9 (370, 200) -> (370, 80)
  line L10 (370, 80) -> (250, 80)
  line L11 (250, 80) -> (250, 200)
  dimension "d102" = 120
  dimension "d103" = 120
  constraint horizontal L8
  constraint vertical L9
  constraint horizontal L10
  constraint vertical L11
  measures "d102" distance of L8.start L8.end
  measures "d103" distance of L8.start L10.end
sketch "Sketch26" plane through (411.6314, 0, 0) normal (1, 0, 0) x (0, 1, 0)
  line L0 (250, 80) -> (370, 80)
  line L1 (370, 80) -> (370, 200)
  line L2 (370, 200) -> (250, 200)
  line L3 (250, 200) -> (250, 80)
  circle A0 centre (310, 140) radius 46
  circle A1 centre (310, 140) radius 48.5
  dimension "d106" = 92
  dimension "d107" = 97
  constraint concentric A0 A1
  measures "d106" diameter of A0
  measures "d107" diameter of A1
sketch "Sketch27" plane through (0, 0, 0) normal (1, 0, 0) x (0, 1, 0)
  line L0 (160, 203) -> (343.2, 203)
  line L1 (353.2, 193) -> (353.2, 9.8)
  line L2 (343.2, -0.2) -> (160, -0.2)
  line L3 (150, 9.8) -> (150, 193)
  arc A0 (160, 203) -> (150, 193) centre (160, 193) ccw
  arc A1 (353.2, 193) -> (343.2, 203) centre (343.2, 193) ccw
  arc A2 (343.2, -0.2) -> (353.2, 9.8) centre (343.2, 9.8) ccw
  arc A3 (150, 9.8) -> (160, -0.2) centre (160, 9.8) ccw
  line L4 (201.6, 161.4) -> (301.6, 161.4)
  line L5 (191.6, 51.4) -> (191.6, 151.4)
  line L6 (301.6, 41.4) -> (201.6, 41.4)
  line L7 (311.6, 151.4) -> (311.6, 51.4)
  arc A4 (201.6, 161.4) -> (191.6, 151.4) centre (201.6, 151.4) ccw
  arc A5 (311.6, 151.4) -> (301.6, 161.4) centre (301.6, 151.4) ccw
  arc A6 (301.6, 41.4) -> (311.6, 51.4) centre (301.6, 51.4) ccw
  arc A7 (191.6, 51.4) -> (201.6, 41.4) centre (201.6, 51.4) ccw
  arc A8 (301.6, 31.4) -> (321.6, 51.4) centre (301.6, 51.4) ccw
  line L8 (321.6, 151.4) -> (321.6, 51.4)
  arc A9 (321.6, 151.4) -> (301.6, 171.4) centre (301.6, 151.4) ccw
  line L9 (201.6, 171.4) -> (301.6, 171.4)
  arc A10 (201.6, 171.4) -> (181.6, 151.4) centre (201.6, 151.4) ccw
  line L10 (181.6, 51.4) -> (181.6, 151.4)
  arc A11 (181.6, 51.4) -> (201.6, 31.4) centre (201.6, 51.4) ccw
  line L11 (301.6, 31.4) -> (201.6, 31.4)
  point P0 (150, 203)
  point P1 (353.2, 203)
  point P2 (150, -0.2)
  dimension "d112" = 203.2
  dimension "d113" = 203.2
  dimension "d114" = 10
  dimension "d116" = 41.6
  dimension "d117" = 41.6
  dimension "d118" = 41.6
  dimension "d119" = 41.6
  dimension "d120" = 10
  dimension "d123" = -10
  constraint horizontal L0
  constraint vertical L1
  constraint horizontal L2
  constraint vertical L3
  constraint coincident P0 L0
  constraint coincident P0 L3
  constraint tangent L0 A0
  constraint tangent L3 A0
  constraint coincident P1 L0
  constraint coincident P1 L1
  constraint tangent L0 A1
  constraint tangent L1 A1
  constraint equal A0 A1
  constraint tangent L1 A2
  constraint tangent L2 A2
  constraint equal A0 A2
  constraint coincident P2 L2
  constraint coincident P2 L3
  constraint tangent L2 A3
  constraint tangent L3 A3
  constraint equal A0 A3
  constraint tangent L4 A4
  constraint tangent L5 A4
  constraint tangent L4 A5
  constraint tangent L7 A5
  constraint equal A4 A5
  constraint tangent L6 A6
  constraint tangent L7 A6
  constraint equal A4 A6
  constraint tangent L5 A7
  constraint tangent L6 A7
  constraint equal A4 A7
  measures "d112" distance of P0 P1
  measures "d113" distance of P0 P2
  measures "d114" radius of A0
  measures "d116" distance of L0 L4
  measures "d117" distance of L3 L5
  measures "d118" distance of L2 L6
  measures "d119" distance of L1 L7
  measures "d120" radius of A4
extrude "Extrude27" add sketch "Sketch27" against normal blind 20 separate body contours L0 L1 L2 L3 A0 A1 A2 A3 | A8 L8 A9 L9 A10 L10 A11 L11 makes body 3
extrude "Extrude28" add sketch "Sketch27" along normal blind 100 separate body contours A8 L8 A9 L9 A10 L10 A11 L11 makes body 4
move_body "Move20" bodies 3 4 to x (1, 0, 0) y (0, 1, 0) z (0, 0, 1) at (-30, 0, 0)
copy_body "CopyPasteBodies1" bodies 3 makes body 5
move_body "Move21" bodies 5 to x (1, 0, 0) y (0, 1, 0) z (0, 0, 1) at (100, 0, 0)
move_body "Move22" bodies 3 5 4 to x (1, 0, 0) y (0, 1, 0) z (0, 0, 1) at (549, -251.73, -243.2447)
move_body "Move23" bodies 1 to x (1, 0, 0) y (0, 1, 0) z (0, 0, 1) at (90, -10.6066, 10.6066)
move_body "Move24" bodies 2 to x (1, 0, 0) y (0, 1, 0) z (0, 0, 1) at (285, -10, 0)
move_body "Move25" bodies 5 4 3 to x (1, 0, 0) y (0, 1, 0) z (0, 0, 1) at (0, 0, 243.45)
move_body "Move26" bodies 1 to x (1, 0, 0) y (0, 1, 0) z (0, 0, 1) at (0, 0, -10.6)
move_body "Move27" bodies 3 4 5 to x (1, 0, 0) y (0, 1, 0) z (0, 0, 1) at (150, 0, 0)
move_body "Move28" bodies 2 to x (1, 0, 0) y (0, 1, 0) z (0, 0, 1) at (-175, 0, 0)
sketch "Sketch28" plane through (0, 0, 203.2223) normal (0, 0, 1) x (-1, 0, 0)
  line L0 (-191.8314, -91.7334) -> (-191.8314, 91.4666)
  line L1 (-191.8314, 91.4666) -> (-496.6314, 91.4666)
  line L2 (-496.6314, 91.4666) -> (-496.6314, -91.7334)
  line L3 (-496.6314, -91.7334) -> (-191.8314, -91.7334)
  line L4 (-486.6314, 81.4666) -> (-486.6314, -81.7334)
  line L5 (-486.6314, -81.7334) -> (-201.8314, -81.7334)
  line L6 (-201.8314, -81.7334) -> (-201.8314, 81.4666)
  line L7 (-201.8314, 81.4666) -> (-486.6314, 81.4666)
  dimension "d126" = -10
extrude "Extrude29" cut sketch "Sketch28" against normal blind 5 contours L4 L5 L6 L7 bodies 1
sketch "Sketch29" plane through (0, 0, 198.7223) normal (0, 0, -1) x (1, 0, 0)
  line L0 (486.6314, 81.4666) -> (486.6314, -81.7334)
  line L1 (486.6314, -81.7334) -> (201.8314, -81.7334)
  line L2 (201.8314, -81.7334) -> (201.8314, 81.4666)
  line L3 (201.8314, 81.4666) -> (486.6314, 81.4666)
  line L4 (191.8314, 86.4666) -> (191.8314, -86.7334)
  line L5 (191.8314, -86.7334) -> (496.6314, -86.7334)
  line L6 (496.6314, -86.7334) -> (496.6314, 86.4666)
  line L7 (496.6314, 86.4666) -> (191.8314, 86.4666)
extrude "Extrude30" add sketch "Sketch29" against normal blind 5 separate body contours L0 L1 L2 L3 makes body 6
extrude "Extrude31" cut 1 faces at (296.7647, 27.3334, 203.7223) along direction (0, 0, -1) blind 2.5 on bodies 6 bodies 6
move_body "Move29" bodies 6 to x (1, 0, 0) y (0, 1, 0) z (0, 0, 1) at (0, 0, 2.5)
sketch "Sketch30" plane through (0, 0, 198.7223) normal (0, 0, -1) x (1, 0, 0)
  line L0 (486.6314, 81.4666) -> (486.6314, -81.7334)
  line L1 (486.6314, -81.7334) -> (201.8314, -81.7334)
  line L2 (201.8314, -81.7334) -> (201.8314, 81.4666)
  line L3 (201.8314, 81.4666) -> (486.6314, 81.4666)
  line L4 (191.8314, 86.4666) -> (191.8314, -86.7334)
  line L5 (191.8314, -86.7334) -> (496.6314, -86.7334)
  line L6 (496.6314, -86.7334) -> (496.6314, 86.4666)
  line L7 (496.6314, 86.4666) -> (191.8314, 86.4666)
  line L8 (206.8314, 76.4666) -> (481.6314, 76.4666)
  line L9 (481.6314, 76.4666) -> (481.6314, -76.7334)
  line L10 (481.6314, -76.7334) -> (206.8314, -76.7334)
  line L11 (206.8314, -76.7334) -> (206.8314, 76.4666)
  dimension "d133" = 5
extrude "Extrude32" add sketch "Sketch30" along normal blind 2.5 separate body contours L0 L1 L2 L3 makes body 7
move_body "Move30" bodies 7 to x (1, 0, 0) y (0, 1, 0) z (0, 0, 1) at (0, 0, 2.5)
sketch "Sketch31" plane through (0, -101.4666, 0) normal (0, -1, 0) x (1, 0, 0)
  line L0 (191.8314, 193.2223) -> (191.8314, 10.0223)
  line L1 (191.8314, 10.0223) -> (496.6314, 10.0223)
  line L2 (496.6314, 10.0223) -> (496.6314, 193.2223)
  line L3 (496.6314, 193.2223) -> (191.8314, 193.2223)
  line L4 (486.6314, 20.0223) -> (486.6314, 183.2223)
  line L5 (486.6314, 183.2223) -> (201.8314, 183.2223)
  line L6 (201.8314, 183.2223) -> (201.8314, 20.0223)
  line L7 (201.8314, 20.0223) -> (486.6314, 20.0223)
  dimension "d136" = -10
extrude "Extrude33" cut sketch "Sketch31" against normal blind 5 contours L4 L5 L6 L7 bodies 1
sketch "Sketch32" plane through (0, -96.4666, 0) normal (0, 1, 0) x (-1, 0, 0)
  line L0 (-486.6314, 20.0223) -> (-486.6314, 183.2223)
  line L1 (-486.6314, 183.2223) -> (-201.8314, 183.2223)
  line L2 (-201.8314, 183.2223) -> (-201.8314, 20.0223)
  line L3 (-201.8314, 20.0223) -> (-486.6314, 20.0223)
  line L4 (-191.8314, 15.5223) -> (-191.8314, 188.7223)
  line L5 (-191.8314, 188.7223) -> (-496.6314, 188.7223)
  line L6 (-496.6314, 188.7223) -> (-496.6314, 15.5223)
  line L7 (-496.6314, 15.5223) -> (-191.8314, 15.5223)
  line L8 (-481.6314, 25.0223) -> (-481.6314, 178.2223)
  line L9 (-481.6314, 178.2223) -> (-206.8314, 178.2223)
  line L10 (-206.8314, 178.2223) -> (-206.8314, 25.0223)
  line L11 (-206.8314, 25.0223) -> (-481.6314, 25.0223)
  dimension "d139" = 5
extrude "Extrude34" add sketch "Sketch32" along normal blind 2.5 separate body contours L0 L1 L2 L3 makes body 8
sketch "Sketch33" plane through (0, -96.4666, 0) normal (0, 1, 0) x (-1, 0, 0)
extrude "Extrude36" add sketch "Sketch32" against normal blind 2.5 separate body contours L0 L1 L2 L3 | L8 L9 L10 L11 makes body 9
move_body "Move31" bodies 8 to x (1, 0, 0) y (0, 1, 0) z (0, 0, 1) at (0, -2.5, 0)
move_body "Move32" bodies 9 to x (1, 0, 0) y (0, 1, 0) z (0, 0, 1) at (0, -2.5, 0)
move_body "Move33" bodies 2 to x (1, 0, 0) y (0, 1, 0) z (0, 0, 1) at (175, 0, 0)
move_body "Move34" bodies 4 5 3 to x (1, 0, 0) y (0, 1, 0) z (0, 0, 1) at (-150, 0, 0)
equation "d71 = 0.00 mm - 10 mm"
named bodies: "Main Tunnel", "Front Air Intake", "Exaust Support 1", "Exaust Holder", "Exhaust Support 2", "Top Acrylic", "Top Acrylic Holder", "Side Acrylic Holder", "Side Acrylic"
